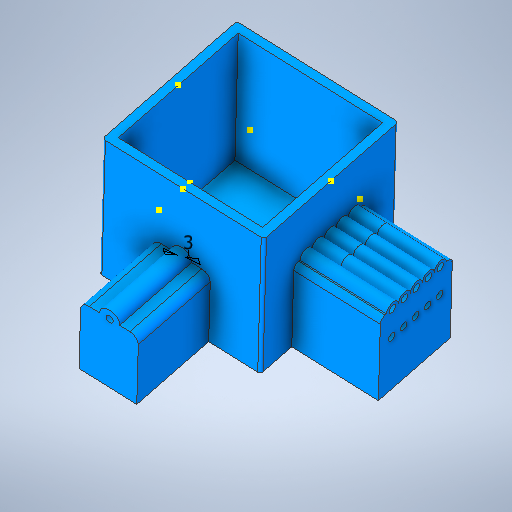
# Autodesk Inventor part: Würfel 1
Saved by Autodesk Inventor 2026.1 (Build 301233020, 233B)
## iProperties
Created: 2025-11-07
Part Number: Würfel 1
Material: Generisch
Document SubType Name: Modeling
Designer: Loabd
Density: 1 g/cm^3
Appearance: Vorgabe
Author: Loabd
Autodesk Inventor part; units mm, degrees
ref_plane "YZ Plane" through (0, 0, 0) normal (1, 0, 0) x (0, 1, 0)
ref_plane "XZ Plane" through (0, 0, 0) normal (0, 1, 0) x (-1, 0, 0)
ref_plane "XY Plane" through (0, 0, 0) normal (0, 0, 1) x (1, 0, 0)
sketch "Skizze1" plane through (0, 0, 0) normal (0, 0, 1) x (1, 0, 0)
  line L0 (-39.2, 0) -> (39.2, 0) construction
  line L1 (0, -39.2) -> (0, 39.2) construction
  line L2 (-25, -25) -> (25, -25)
  line L3 (25, -25) -> (25, 25)
  line L4 (25, 25) -> (-25, 25)
  line L5 (-25, 25) -> (-25, -25)
  line L6 (-25, -25) -> (25, 25) construction
  line L7 (25, -25) -> (-25, 25) construction
  line L8 (-28, -28) -> (28, -28)
  line L9 (28, -28) -> (28, 28)
  line L10 (28, 28) -> (-28, 28)
  line L11 (-28, 28) -> (-28, -28)
  line L12 (-28, -28) -> (28, 28) construction
  line L13 (28, -28) -> (-28, 28) construction
  point P0 (0, 0)
  dimension "d0" = 50
  dimension "d1" = 50
  dimension "d2" = 56
  dimension "d3" = 56
  constraints: 24 end point, 4 midpoint, 4 parallel, 2 horizontal, 2 perpendicular
  measures "d0" distance of L4.end L3.end
  measures "d1" distance of L3.end L2.end
  measures "d2" distance of L10.end L9.end
  measures "d3" distance of L9.end L8.end
extrude "Extrusion1" add sketch "Skizze1" along normal blind 50
sketch "Skizze2" plane through (0, 0, 50) normal (0, 0, 1) x (1, 0, 0)
  line L0 (-28, -28) -> (28, -28)
  line L1 (28, -28) -> (28, 28)
  line L2 (28, 28) -> (-28, 28)
  line L3 (-28, 28) -> (-28, -28)
  line L4 (-28, -28) -> (28, 28) construction
  line L5 (28, -28) -> (-28, 28) construction
  point P0 (0, 0)
  dimension "d6" = 56
  dimension "d7" = 56
  constraints: 12 end point, 2 midpoint, 2 parallel, 1 horizontal, 1 perpendicular
  measures "d6" distance of L2.end L1.end
  measures "d7" distance of L1.end L0.end
extrude "Extrusion2" add sketch "Skizze2" along normal blind 3
sketch "Skizze3" plane through (28, -28, 0) normal (1, 0, 0) x (0, 0, -1)
  circle A0 centre (-26.5, 28) radius 1.5
  point P0 (0, 28)
  dimension "d10" = 3
  constraints: 1 centre point
  measures "d10" diameter of A0
extrude "Extrusion3" cut sketch "Skizze3" against normal blind 3
sketch "Skizze4" plane through (28, -28, 0) normal (1, 0, 0) x (0, 0, -1)
  point P0 (0, 28)
sketch "Skizze5" plane through (-28, -28, 0) normal (0, -1, 0) x (1, 0, 0)
  circle A0 centre (28, 21) radius 1
  circle A1 centre (28, 32) radius 1
  point P0 (28, 0)
  dimension "d13" = 2
  dimension "d14" = 2
  constraints: 2 centre point
  measures "d13" diameter of A0
  measures "d14" diameter of A1
sketch "Skizze6" plane through (-28, -28, 0) normal (0, -1, 0) x (1, 0, 0)
  circle A0 centre (23, 21.0101) radius 1
  circle A1 centre (18, 21.0101) radius 1
  circle A2 centre (33, 21.01) radius 1
  circle A3 centre (38, 21.01) radius 1
  circle A4 centre (23, 32.002) radius 1
  circle A5 centre (18, 32.002) radius 1
  circle A6 centre (33, 32.002) radius 1
  circle A7 centre (38, 32.002) radius 1
  point P0 (28, 0)
  dimension "d15" = 2
  dimension "d16" = 2
  dimension "d17" = 2
  dimension "d18" = 2
  dimension "d19" = 2
  dimension "d20" = 2
  dimension "d21" = 2
  dimension "d22" = 2
  constraints: 8 centre point
  measures "d15" diameter of A0
  measures "d16" diameter of A1
  measures "d17" diameter of A2
  measures "d18" diameter of A3
  measures "d19" diameter of A4
  measures "d20" diameter of A5
  measures "d21" diameter of A6
  measures "d22" diameter of A7
extrude "Extrusion4" cut sketch "Skizze6" against normal blind 3
sketch "Skizze7" plane through (-28, -28, 0) normal (0, -1, 0) x (1, 0, 0)
  circle A0 centre (28, 21.008) radius 1
  circle A1 centre (28, 32.0114) radius 1
  point P0 (28, 0)
  dimension "d25" = 2
  dimension "d26" = 2
  constraints: 2 centre point
  measures "d25" diameter of A0
  measures "d26" diameter of A1
extrude "Extrusion5" cut sketch "Skizze7" against normal blind 3
sketch "Skizze8" plane through (28, -28, 0) normal (1, 0, 0) x (0, 0, -1)
  circle A0 centre (-26.5, 28) radius 1.5 projected
  circle A1 centre (-26.5, 28) radius 1.5
  circle A2 centre (-26.5, 28) radius 3.5
  point P0 (0, 28)
  dimension "d29" = 3
  dimension "d30" = 7
  constraints: 2 centre point, 2 coincident
  measures "d29" diameter of A1
  measures "d30" diameter of A2
extrude "Extrusion6" add sketch "Skizze8" along normal blind 10
sketch "Skizze9" plane through (28, -28, 0) normal (1, 0, 0) x (0, 0, -1)
  point P0 (0, 28)
extrude "Extrusion7" add sketch "Skizze3" against normal blind 3
extrude "Extrusion8" cut sketch "Skizze3" against normal blind 3
sketch "Skizze10" plane through (25, -25, 0) normal (-1, 0, 0) x (0, 0, 1)
  point P0 (0, 25)
sketch "Skizze11" plane through (-28, -28, 0) normal (0, -1, 0) x (1, 0, 0)
  point P0 (28, 0)
sketch "Skizze12" plane through (-28, -28, 0) normal (0, -1, 0) x (1, 0, 0)
  circle A0 centre (18, 32.002) radius 1 projected
  circle A1 centre (18, 32.002) radius 2.5
  circle A2 centre (23, 32.002) radius 2.5
  circle A3 centre (28, 32.002) radius 2.5
  circle A4 centre (33, 32.0114) radius 2.5
  circle A5 centre (38, 32.0114) radius 2.5
  circle A6 centre (18, 21.0101) radius 1 projected
  circle A7 centre (18, 21.0101) radius 2.5
  circle A8 centre (23, 21.0101) radius 2.5
  circle A9 centre (28, 21.0101) radius 2.5
  circle A10 centre (33, 21.0101) radius 2.5
  circle A11 centre (38, 21.01) radius 2.5
  point P0 (28, 0)
  point P1 (20.5, 21.0101)
  point P2 (25.5, 21.0101)
  point P3 (30.5, 21.0101)
  point P4 (35.5, 21.0101)
  point P5 (35.5, 32.0114)
  point P6 (30.5, 32.0067)
  point P7 (25.5, 32.002)
  point P8 (20.5, 32.002)
  dimension "d37" = 5
  dimension "d38" = 5
  dimension "d39" = 5
  dimension "d40" = 5
  dimension "d41" = 5
  dimension "d42" = 5
  dimension "d43" = 5
  dimension "d44" = 5
  dimension "d45" = 5
  dimension "d46" = 5
  constraints: 10 centre point, 2 coincident
  measures "d37" diameter of A1
  measures "d38" diameter of A2
  measures "d39" diameter of A3
  measures "d40" diameter of A4
  measures "d41" diameter of A5
  measures "d42" diameter of A7
  measures "d43" diameter of A8
  measures "d44" diameter of A9
  measures "d45" diameter of A10
  measures "d46" diameter of A11
extrude "Extrusion9" add sketch "Skizze12" along normal blind 10
sketch "Skizze13" plane through (-28, -28, 0) normal (0, -1, 0) x (1, 0, 0)
  point P0 (28, 0)
sketch "Skizze14" plane through (-25, 25, 0) normal (0, -1, 0) x (1, 0, 0)
  point P0 (25, 0)
sketch "Skizze15" plane through (-28, -28, 0) normal (0, -1, 0) x (1, 0, 0)
  point P0 (28, 0)
extrude "Extrusion10" cut sketch "Skizze5" along normal through all contours A1
sketch "Skizze16" plane through (10, -38, 21.01) normal (0, -1, 0) x (1, 0, 0)
  circle A0 centre (0, 0) radius 2.5 projected
  circle A1 centre (0, 0) radius 1
  circle A2 centre (-5, 0) radius 1
  circle A3 centre (-10, 0.0001) radius 1
  circle A4 centre (-15, 0.0001) radius 1
  point P0 (-10, -21.01)
  point P1 (-2.5, 0.0001)
  dimension "d51" = 2
  dimension "d52" = 2
  dimension "d53" = 2
  dimension "d54" = 2
  constraints: 4 centre point, 1 coincident, 1 other
  measures "d51" diameter of A1
  measures "d52" diameter of A2
  measures "d53" diameter of A3
  measures "d54" diameter of A4
extrude "Extrusion11" cut sketch "Skizze16" against normal blind 10 contours A1
sketch "Skizze17" plane through (-28, -38, 0) normal (0, -1, 0) x (1, 0, 0)
  point P0 (28, 0)
sketch "Skizze18" plane through (-28, -38, 0) normal (0, -1, 0) x (1, 0, 0)
  circle A0 centre (33, 21.01) radius 1 projected
  circle A1 centre (33, 21.01) radius 1
  point P0 (28, 0)
  dimension "d57" = 2
  constraints: 1 centre point, 1 coincident
  measures "d57" diameter of A1
extrude "Extrusion12" cut sketch "Skizze18" against normal blind 10
sketch "Skizze19" plane through (-28, -38, 0) normal (0, -1, 0) x (1, 0, 0)
  circle A0 centre (28, 21.008) radius 1 projected
  circle A1 centre (28, 21.008) radius 1
  circle A2 centre (23, 21.0101) radius 1 projected
  circle A3 centre (23, 21.0101) radius 1
  point P0 (28, 0)
  dimension "d60" = 2
  dimension "d61" = 2
  constraints: 2 centre point, 2 coincident
  measures "d60" diameter of A1
  measures "d61" diameter of A3
extrude "Extrusion13" cut sketch "Skizze19" against normal blind 10
sketch "Skizze20" plane through (10, -38, 32.0114) normal (0, -1, 0) x (1, 0, 0)
  circle A0 centre (0, -0.0094) radius 1 projected
  circle A1 centre (0, -0.0094) radius 1
  circle A2 centre (-15, -0.0094) radius 1 projected
  circle A3 centre (-15, -0.0094) radius 1
  arc A4 (-2.5, 0) -> (-7.5, -0.0047) centre (-5, 0) ccw projected
  circle A5 centre (-5, 0) radius 1
  point P0 (-10, -32.0114)
  dimension "d64" = 2
  dimension "d65" = 2
  dimension "d66" = 2
  constraints: 3 centre point, 3 coincident
  measures "d64" diameter of A1
  measures "d65" diameter of A3
  measures "d66" diameter of A5
extrude "Extrusion14" cut sketch "Skizze20" against normal blind 10
sketch "Skizze21" plane through (-10, -38, 32.002) normal (0, -1, 0) x (1, 0, 0)
  point P0 (10, -32.002)
sketch "Skizze22" plane through (-10, -38, 32.002) normal (0, -1, 0) x (1, 0, 0)
  point P0 (10, -32.002)
sketch "Skizze23" plane through (-28, -28, 0) normal (0, -1, 0) x (1, 0, 0)
  line L0 (13, 21.0101) -> (43, 21.0101)
  line L1 (43, 21.0101) -> (43, 53)
  line L2 (43, 53) -> (13, 53)
  line L3 (13, 53) -> (13, 21.0101)
  point P0 (28, 0)
  dimension "d69" = 30
  constraints: 8 end point, 2 parallel, 1 horizontal, 1 perpendicular
  measures "d69" distance of L0.start L0.end
extrude "Extrusion15" add sketch "Skizze23" along normal blind 10
sketch "Skizze24" plane through (-28, -38, 0) normal (0, -1, 0) x (1, 0, 0)
  line L0 (37, 21.0101) -> (39, 21.0101) projected
  circle A0 centre (38, 21.0101) radius 1
  circle A1 centre (33, 21.0101) radius 1
  circle A2 centre (28, 21.0101) radius 1
  circle A3 centre (23, 21.0101) radius 1
  circle A4 centre (18, 21.0101) radius 1
  point P0 (28, 0)
  dimension "d72" = 2
  dimension "d73" = 2
  dimension "d74" = 2
  dimension "d75" = 2
  dimension "d76" = 2
  constraints: 5 centre point, 1 midpoint
  measures "d72" diameter of A0
  measures "d73" diameter of A1
  measures "d74" diameter of A2
  measures "d75" diameter of A3
  measures "d76" diameter of A4
extrude "Extrusion16" cut sketch "Skizze24" against normal blind 10
sketch "Skizze25" plane through (-28, -38, 0) normal (0, -1, 0) x (1, 0, 0)
  point P0 (28, 0)
sketch "Skizze26" plane through (-28, -38, 0) normal (0, -1, 0) x (1, 0, 0)
  circle A0 centre (38, 32.002) radius 1 projected
  circle A1 centre (38, 32.002) radius 1
  circle A2 centre (33, 32.002) radius 1 projected
  circle A3 centre (33, 32.002) radius 1
  circle A4 centre (28, 32.0114) radius 1 projected
  circle A5 centre (28, 32.0114) radius 1
  circle A6 centre (23, 32.002) radius 1 projected
  circle A7 centre (23, 32.002) radius 1
  circle A8 centre (18, 32.002) radius 1 projected
  circle A9 centre (18, 32.002) radius 1
  point P0 (28, 0)
  dimension "d79" = 2
  dimension "d80" = 2
  dimension "d81" = 2
  dimension "d82" = 2
  dimension "d83" = 2
  constraints: 5 centre point, 5 coincident
  measures "d79" diameter of A1
  measures "d80" diameter of A3
  measures "d81" diameter of A5
  measures "d82" diameter of A7
  measures "d83" diameter of A9
extrude "Extrusion17" cut sketch "Skizze26" against normal blind 10
sketch "Skizze27" plane through (-28, -38, 0) normal (0, -1, 0) x (1, 0, 0)
  point P0 (28, 0)
sketch "Skizze28" plane through (-28, -38, 0) normal (0, -1, 0) x (1, 0, 0)
  point P0 (28, 0)
fillet "Rundung1" radius 2 1 edges at (15, -33, 21.0101)
fillet "Rundung2" radius 2 1 edges at (-15, -33, 21.0101)
sketch "Skizze29" plane through (28, -28, 0) normal (1, 0, 0) x (0, 0, -1)
  point P0 (0, 28)
sketch "Skizze30" plane through (28, -28, 0) normal (1, 0, 0) x (0, 0, -1)
  line L0 (-26.5, 18) -> (-26.5, 38)
  line L1 (-26.5, 38) -> (-53, 38)
  line L2 (-53, 38) -> (-53, 18)
  line L3 (-53, 18) -> (-26.5, 18)
  point P0 (0, 28)
  dimension "d88" = 20
  constraints: 8 end point, 2 parallel, 1 perpendicular, 1 vertical
  measures "d88" distance of L0.start L0.end
extrude "Extrusion18" add sketch "Skizze30" along normal blind 10
sketch "Skizze31" plane through (38, -28, 0) normal (1, 0, 0) x (0, 0, -1)
  line L0 (-26.5, 26.5) -> (-26.5, 29.5) projected
  circle A0 centre (-26.5, 28) radius 1.5
  point P0 (0, 28)
  dimension "d91" = 3
  constraints: 1 centre point, 1 midpoint
  measures "d91" diameter of A0
extrude "Extrusion19" cut sketch "Skizze31" against normal blind 10
fillet "Rundung3" radius 3 1 edges at (33, -10, 26.5)
fillet "Rundung4" radius 3 1 edges at (33, 10, 26.5)
fillet "Rundung5" radius 1 1 edges at (-28, -28, 26.5)
fillet "Rundung6" radius 1 1 edges at (-28, 28, 26.5)
fillet "Rundung7" radius 1 1 edges at (28, 28, 26.5)
sketch "Skizze32" plane through (28, 0, 26.5) normal (1, 0, 0) x (0, 0, -1)
  point P0 (26.5, 0)
sketch "Skizze33" plane through (38, -28, 0) normal (1, 0, 0) x (0, 0, -1)
  point P0 (0, 28)
fillet "Rundung9" radius 1 1 edges at (28, -28, 26.5)
sketch "Skizze34" plane through (38, -28, 0) normal (1, 0, 0) x (0, 0, -1)
  point P0 (0, 28)
sketch "Skizze35" plane through (0, 0, 0) normal (0, 0, -1) x (-1, 0, 0)
  point P0 (0, 0)
sketch "Skizze36" plane through (28, 0, 26.5) normal (1, 0, 0) x (0, 0, -1)
  point P0 (26.5, 0)
sketch "Skizze37" plane through (38, -28, 0) normal (1, 0, 0) x (0, 0, -1)
  circle A0 centre (-26.5, 28) radius 1.5 projected
  circle A1 centre (-26.5, 28) radius 1.5
  point P0 (0, 28)
  constraints: 1 centre point, 1 coincident
extrude "Extrusion20" add sketch "Skizze37" against normal blind 13
sketch "Skizze38" plane through (38, -28, 0) normal (1, 0, 0) x (0, 0, -1)
  arc A0 (-26.5, 24.5) -> (-26.5, 31.5) centre (-26.5, 28) ccw projected
  circle A1 centre (-26.5, 28) radius 1.3
  point P0 (0, 28)
  dimension "d103" = 2.6
  constraints: 1 centre point, 1 coincident
  measures "d103" diameter of A1
extrude "Extrusion21" cut sketch "Skizze38" against normal blind 13
sketch "Skizze39" plane through (38, -28, 0) normal (1, 0, 0) x (0, 0, -1)
  point P0 (0, 28)
sketch "Skizze40" plane through (38, -28, 0) normal (1, 0, 0) x (0, 0, -1)
  point P0 (0, 28)
sketch "Skizze42" plane through (38, -28, 0) normal (1, 0, 0) x (0, 0, -1)
  line L0 (-53, 38) -> (-53, 18) projected
  line L1 (-53, 18) -> (-29.5, 18)
  line L2 (-26.5, 21) -> (-26.5, 35)
  line L3 (-29.5, 38) -> (-53, 38)
  line L4 (-53, 38) -> (-53, 18)
  line L5 (-29.5, 38) -> (-53, 38) projected
  line L6 (-26.5, 31.5) -> (-26.5, 35) projected
  arc A0 (-29.5, 18) -> (-26.5, 21) centre (-29.5, 21) ccw
  arc A1 (-26.5, 35) -> (-29.5, 38) centre (-29.5, 35) ccw
  line L7 (-26.5, 24.5) -> (-26.5, 24.5)
  line L8 (-23, 28) -> (-23, 28)
  line L9 (-26.5, 31.5) -> (-26.5, 31.5)
  line L10 (-26.5, 31.5) -> (-26.5, 24.5)
  arc A2 (-26.5, 24.5) -> (-26.5, 31.5) centre (-26.5, 28) ccw projected
  arc A3 (-26.5, 24.5) -> (-23, 28) centre (-26.5, 28) ccw
  arc A4 (-23, 28) -> (-26.5, 31.5) centre (-26.5, 28) ccw
  circle A5 centre (-26.5, 28) radius 1.3
  point P0 (0, 28)
  dimension "d106" = 3
  dimension "d107" = 3.5
  constraints: 16 end point, 9 tangent, 8 point on circle, 5 centre point, 4 parallel, 2 collinear, 2 equal radius, 2 horizontal, 2 perpendicular, 1 coincident, 1 midpoint
  measures "d106" radius of A0
  measures "d107" radius of A3
extrude "Extrusion22" add sketch "Skizze42" along normal blind 20 contours L3 A1 L2 A5 A0 L1 L0 | A2 L2 A5
sketch "Skizze43" plane through (-28, -38, 0) normal (0, -1, 0) x (1, 0, 0)
  line L0 (43, 53) -> (55, 53) projected
  line L1 (43, 53) -> (13, 53)
  line L2 (13, 53) -> (13, 23.0101)
  line L3 (15, 21.0101) -> (41, 21.0101)
  line L4 (43, 23.0101) -> (43, 53)
  line L5 (13, 53) -> (13, 23.0101) projected
  line L6 (15, 21.0101) -> (15.5, 21.0101) projected
  circle A0 centre (38, 21.0101) radius 1.0001
  arc A1 (39, 21.0101) -> (37, 21.0101) centre (38, 21.0101) ccw projected
  arc A2 (37, 21.0101) -> (39, 21.0101) centre (38, 21.01) ccw projected
  circle A3 centre (38, 21.01) radius 2.5
  arc A4 (35.5, 21.0101) -> (40.5, 21.0101) centre (38, 21.01) ccw projected
  circle A5 centre (33, 21.01) radius 2.5
  circle A6 centre (33, 21.0101) radius 1.0001
  circle A7 centre (28, 21.01) radius 2.5
  circle A8 centre (28, 21.0101) radius 1.0001
  circle A9 centre (23, 21.01) radius 2.5
  circle A10 centre (23, 21.0101) radius 1.0001
  circle A11 centre (18, 21.01) radius 2.5
  circle A12 centre (18, 21.0101) radius 1.0001
  arc A13 (41, 21.0101) -> (43, 23.0101) centre (41, 23.0101) ccw
  arc A14 (13, 23.0101) -> (15, 21.0101) centre (15, 23.0101) ccw
  circle A15 centre (38, 32.002) radius 1
  circle A16 centre (38, 32.002) radius 1 projected
  circle A17 centre (33, 32.002) radius 1
  circle A18 centre (28, 32.002) radius 1
  circle A19 centre (23, 32.002) radius 1
  circle A20 centre (18, 32.002) radius 1
  point P0 (28, 0)
  point P1 (16.9999, 21.0101)
  point P2 (19.0001, 21.0101)
  point P3 (21.9999, 21.0101)
  point P4 (24.0001, 21.0101)
  point P5 (26.9999, 21.0101)
  point P6 (29.0001, 21.0101)
  point P7 (31.9999, 21.0101)
  point P8 (34.0001, 21.0101)
  point P9 (36.9999, 21.0101)
  point P10 (39.0001, 21.0101)
  dimension "d112" = 5
  dimension "d117" = 2
  dimension "d120" = 5
  constraints: 17 centre point, 8 end point, 7 tangent, 4 point on circle, 3 concentric, 3 horizontal, 2 collinear, 2 parallel, 1 coincident, 1 equal radius, 1 perpendicular, 1 point on line, 24 other
  measures "d112" distance of A3.centre A5.centre
  measures "d117" radius of A13
  measures "d120" distance of A15.centre A17.centre
extrude "Extrusion23" add sketch "Skizze43" along normal blind 20 contours L4 A13 L3 A3 A5 A7 A9 A11 A14 L2 L1 | L3 A0 A3 | A11 L3 A12 | L3 A6 A5 | A9 L3 A10 | L3 A8 A7 picked at (36.0339, 21.2893) picked at (16.0242, 21.2095) picked at (31.0242, 21.2095) picked at (21.0242, 21.2095) picked at (26.0242, 21.2095)
sketch "Skizze44" plane through (-28, -38, 0) normal (0, -1, 0) x (1, 0, 0)
  circle A0 centre (38, 21.01) radius 1
  arc A1 (37, 21.0101) -> (39, 21.0101) centre (38, 21.01) ccw projected
  circle A2 centre (38, 21.01) radius 2.5
  arc A3 (35.5, 21.0101) -> (40.5, 21.0101) centre (38, 21.01) ccw projected
  line L0 (38, 21.01) -> (8.999, 21.01) construction
  circle A4 centre (33, 21.01) radius 2.5
  circle A5 centre (33, 21.01) radius 1
  circle A6 centre (28, 21.01) radius 2.5
  circle A7 centre (28, 21.01) radius 1
  circle A8 centre (23, 21.01) radius 2.5
  circle A9 centre (23, 21.01) radius 1
  circle A10 centre (18, 21.01) radius 2.5
  circle A11 centre (18, 21.01) radius 1
  point P0 (28, 0)
  point P1 (20.5, 21.01)
  point P2 (25.5, 21.01)
  point P3 (30.5, 21.01)
  point P4 (35.5, 21.01)
  dimension "d129" = 5
  constraints: 10 centre point, 4 concentric, 2 end point, 2 horizontal, 16 other
  measures "d129" distance of A2.centre A4.centre
extrude "Extrusion24" add sketch "Skizze44" along normal blind 20
sketch "Skizze45" plane through (-28, -58, 0) normal (0, -1, 0) x (1, 0, 0)
  circle A0 centre (38, 21.01) radius 1.375
  arc A1 (36.9999, 21.0101) -> (39.0001, 21.0101) centre (38, 21.01) ccw projected
  line L0 (21.9032, 5.8818) -> (35.645, 5.8818) construction
  line L1 (35.645, 5.8818) -> (35.645, 13.732) construction
  circle A2 centre (33, 21.01) radius 1.375
  circle A3 centre (28, 21.01) radius 1.375
  circle A4 centre (23, 21.01) radius 1.375
  circle A5 centre (18, 21.01) radius 1.375
  circle A6 centre (38, 32.01) radius 1.375
  circle A7 centre (33, 32.01) radius 1.375
  circle A8 centre (28, 32.01) radius 1.375
  circle A9 centre (23, 32.01) radius 1.375
  circle A10 centre (18, 32.01) radius 1.375
  point P0 (28, 0)
  dimension "d136" = 2.75
  dimension "d139" = 5
  dimension "d142" = 11
  constraints: 10 centre point, 4 end point, 2 horizontal, 1 perpendicular, 1 vertical, 20 other
  measures "d136" diameter of A0
  measures "d139" distance of A0.centre A2.centre
  measures "d142" distance of A0.centre A6.centre
extrude "Extrusion25" cut sketch "Skizze45" against normal blind 50 contours A0
pattern_linear "Rechteckige Anordnung1" count 5 spacing 5 along (-1, 0, 0) count 2 spacing 11 along (0, 0, 1) of "Extrusion25"
